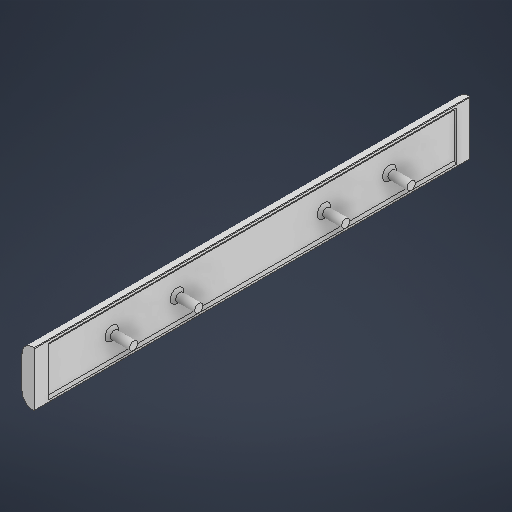
# Autodesk Inventor part: 后板
Saved by Autodesk Inventor 2025 (Build 290162000, 162)
## iProperties
Created: 2025-08-27
Part Number: 后板
Material: 常规
Document SubType Name: Modeling
Designer: HZD
Density: 1 g/cm^3
Appearance: 默认
Author: HZD
Autodesk Inventor part; units mm, degrees
ref_plane "YZ Plane" through (0, 0, 0) normal (1, 0, 0) x (0, 1, 0)
sketch "草图1" plane through (0, 0, 0) normal (0, 0, 1) x (1, 0, 0)
  line L0 (0, 0) -> (0, 6) construction
  line L1 (2, 0) -> (2, 6)
  line L2 (-2, 6) -> (-2, 0)
  arc A0 (-2, 0) -> (2, 0) centre (0, 0) ccw
  arc A1 (2, 6) -> (-2, 6) centre (0, 6) ccw
  point P0 (0, 3)
  dimension "d0" = 4
  dimension "d1" = 6
  constraints: 8 end point, 4 point on circle, 4 tangent, 2 centre point, 1 midpoint, 1 parallel, 1 vertical
  measures "d0" distance between parallel lines of L2 L1
  measures "d1" distance of L0.start L0.end
extrude "拉伸1" add sketch "草图1" along normal blind 80
ref_plane "工作平面1" through (0, 0, 40) normal (0, 0, 1) x (1, 0, 0)
sketch "草图2" plane through (0, 0, 40) normal (0, 0, 1) x (1, 0, 0)
  arc A0 (2, 6) -> (-2, 6) centre (0, 6) ccw projected
  line L0 (-2, 6) -> (-2, 0) projected
  arc A1 (-2, 0) -> (2, 0) centre (0, 0) ccw projected
  line L1 (2, 0) -> (2, 6) projected
  line L2 (0.3, 7.9774) -> (0.3, -1.9774)
  dimension "d7" = 2.3
  constraints: 2 end point, 2 point on circle, 1 vertical
  measures "d7" distance between parallel lines of L0 L2
extrude "拉伸2" cut sketch "草图2" along normal mid plane 80 contours L1 A1 L2 A0
fillet "圆角1" radius 0.1 2 edges at (0.3, -1.9774, 40) (0.3, 7.9774, 40)
ref_plane "工作平面2" through (0, 0, 40) normal (0, 0, -1) x (-1, 0, 0)
sketch "草图4" plane through (0, 0, 40) normal (0, 0, -1) x (-1, 0, 0)
  line L0 (-1.3425, 7.4877) -> (0, 7.4877)
  line L1 (0, 7.4877) -> (0, -1.5123)
  line L2 (0, -1.5123) -> (-1.3425, -1.5123)
  line L3 (-1.3425, -1.5123) -> (-1.3425, 7.4877)
  line L4 (2, 6) -> (2, 0) projected
  point P0 (0, 0)
  dimension "d9" = 9
  dimension "d30" = 2
  constraints: 8 end point, 2 parallel, 1 horizontal, 1 perpendicular
  measures "d9" distance of L2.end L0.start
  measures "d30" distance between parallel lines of L4 L1
extrude "拉伸3" cut sketch "草图4" along normal mid plane 75
fillet "圆角2" radius 0.5 2 edges at (0, 7.4877, 40) (0, -1.5123, 40)
sketch "草图7" plane through (0, -1.054, 2.5) normal (1, 0, 0) x (0, 0, -1)
  line L0 (0, 6.0123) -> (-75, 6.0123)
  line L1 (-75, 6.0123) -> (-75, 2.0123)
  line L2 (-75, 2.0123) -> (0, 2.0123)
  line L3 (0, 2.0123) -> (0, 6.0123)
  line L4 (-29.9948, 2.5123) -> (-31.9948, 2.5123) projected
  line L5 (-29.9948, 5.5123) -> (-31.9948, 5.5123) projected
  line L6 (0, 8.5417) -> (0, -0.4583) projected
  line L7 (-22.5, 6.0123) -> (-25.5, 6.0123) projected
  line L8 (-25.5, 6.0123) -> (-25.5, 2.0123) projected
  line L9 (-25.5, 2.0123) -> (-22.5, 2.0123) projected
  circle A0 centre (-24, 4.0123) radius 0.75
  circle A1 centre (-12, 4.0123) radius 0.75
  line L10 (-75, -0.4583) -> (-75, 8.5417) projected
  line L11 (-75, 8.0835) -> (0, 8.0835) projected
  line L12 (-37.5, 8.0835) -> (-37.5, -7.1679)
  circle A2 centre (-51, 4.0123) radius 0.75
  circle A3 centre (-63, 4.0123) radius 0.75
  circle A4 centre (-24, 4.0123) radius 1.75
  circle A5 centre (-12, 4.0123) radius 1.75
  circle A6 centre (-51, 4.0123) radius 1.75
  circle A7 centre (-63, 4.0123) radius 1.75
  point P0 (2.5, 1.054)
  point P1 (0, 4.0123)
  point P2 (0, 8.9096)
  point P3 (0, -0.8851)
  point P4 (-25.5, 3.1109)
  point P5 (-25.5, 4.9137)
  dimension "d31" = 1
  dimension "d32" = 1
  dimension "d33" = 1
  dimension "d35" = 1
  dimension "d36" = 1.5
  dimension "d37" = 1.5
  constraints: 10 end point, 8 centre point, 3 collinear, 2 midpoint, 2 parallel, 2 symmetric about line, 1 horizontal, 1 perpendicular, 1 vertical, 2 other
  measures "d31" radial gap between concentric circles of A0 A4
  measures "d32" radial gap between concentric circles of A1 A5
  measures "d33" radial gap between concentric circles of A2 A6
  measures "d35" radial gap between concentric circles of A3 A7
  measures "d36" diameter of A1
  measures "d37" diameter of A0
extrude "拉伸6" add sketch "草图7" along normal blind 4 contours A0 | A1
chamfer "倒角2" distance 0.5 angle 45 2 edges at (0, 2.9583, 27.25) (0, 2.9583, 15.25)
mirror "镜像2" about plane through (0, 0, 40) normal (0, 0, -1) of "拉伸6", "倒角2"
sketch "草图10" plane through (0, 2.9583, 14.5) normal (1, 0, 0) x (0, 0, -1)
  circle A0 centre (0, 0) radius 1 projected
  circle A1 centre (-12, 0) radius 1 projected
  circle A2 centre (-51, 0) radius 1 projected
  circle A3 centre (-39, 0) radius 1 projected
  point P0 (14.5, -2.9583)
sketch "草图12" plane through (0, -1.054, 2.5) normal (1, 0, 0) x (0, 0, -1)
  circle A0 centre (-24, 4.0123) radius 1 projected
  line L0 (-24, 4.0123) -> (0, 4.0417)
  line L1 (0, 8.5417) -> (0, -0.4583) projected
  line L2 (2.5, 2.5153) -> (-22.2302, 2.5153)
  line L3 (-22.2302, 2.5153) -> (-22.2302, 5.5153)
  line L4 (-22.2302, 5.5153) -> (2.5, 5.5153)
  line L5 (2.5, 5.5153) -> (2.5, 2.5153)
  line L6 (0, 0) -> (-75, 0) projected
  line L7 (0, 0) -> (0, 8.0835) projected
  line L8 (-75, 8.0835) -> (0, 8.0835) projected
  line L9 (-75, 8.0835) -> (-75, 0) projected
  circle A1 centre (-12, 4.0123) radius 1 projected
  line L10 (2.5, 8.9435) -> (2.5, -0.8354) projected
  line L11 (-75, 8.5417) -> (0, 8.5417) projected
  line L12 (0, -0.4583) -> (-75, -0.4583) projected
  point P0 (2.5, 1.054)
  point P1 (212.7603, 4.3031)
  point P2 (-23.8907, 5.0063)
  point P3 (-23.1375, 3.5063)
  point P4 (0, 5.5153)
  point P5 (0, 2.5153)
  point P6 (-24.1093, 5.0063)
  point P7 (-21.5, 4.0153)
  dimension "d47" = 3
  dimension "d48" = 1.5
  constraints: 10 end point, 4 parallel, 2 point on line, 1 collinear, 1 horizontal, 1 midpoint
  measures "d47" distance between parallel lines of L4 L2
  measures "d48" distance from line of point (-21.5, 4.015) L2
